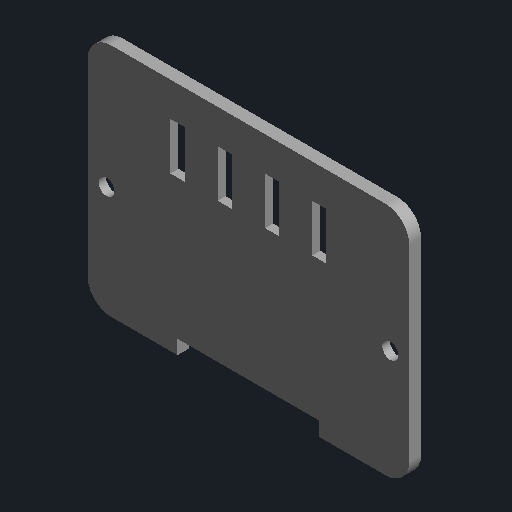
# Autodesk Inventor part: Torso_espalda
Saved by Autodesk Inventor 2027 (Build 310192060, 192F)
## iProperties
Part Number: Torso_espalda
Material: Genérico
Document SubType Name: Modelado
Designer: rodri
Appearance: Por defecto
Author: rodri
Autodesk Inventor part; units mm, degrees
ref_plane "Plano de trabajo1" through (0, 0, -29.2) normal (0, 0, 1) x (1, 0, 0)
sketch "Boceto1" plane through (0, 0, -29.2) normal (0, 0, 1) x (1, 0, 0)
  line L0 (-34, 8) -> (34, 8)
  line L1 (34, 8) -> (34, 57.7)
  line L2 (34, 57.7) -> (-34, 57.7)
  line L3 (-34, 57.7) -> (-34, 8)
  constraints: 8 end point, 2 parallel, 1 horizontal, 1 perpendicular
extrude "Extrusión1" add sketch "Boceto1" along normal blind 2.5
fillet "Empalme1" radius 5 4 edges at (-34, 8, -27.95) (-34, 57.7, -27.95) (34, 57.7, -27.95) (34, 8, -27.95)
ref_plane "Plano de trabajo2" through (0, 0, -29.3) normal (0, 0, 1) x (1, 0, 0)
sketch "Boceto2" plane through (0, 0, -29.3) normal (0, 0, 1) x (1, 0, 0)
  circle A0 centre (30, 31.3) radius 1.7
  circle A1 centre (-30, 31.3) radius 1.7
  constraints: 2 centre point
extrude "Extrusión2" cut sketch "Boceto2" along normal blind 2.7
ref_plane "Plano de trabajo3" through (0, 0, -29.3) normal (0, 0, 1) x (1, 0, 0)
sketch "Boceto3" plane through (0, 0, -29.3) normal (0, 0, 1) x (1, 0, 0)
  circle A0 centre (30, 31.3) radius 2.9
  circle A1 centre (-30, 31.3) radius 2.9
  constraints: 2 centre point
extrude "Extrusión3" cut sketch "Boceto3" along normal blind 1
ref_plane "Plano de trabajo4" through (0, 0, -29.3) normal (0, 0, 1) x (1, 0, 0)
sketch "Boceto4" plane through (0, 0, -29.3) normal (0, 0, 1) x (1, 0, 0)
  line L0 (-22, 38) -> (22, 38)
  line L1 (22, 38) -> (22, 53)
  line L2 (22, 53) -> (-22, 53)
  line L3 (-22, 53) -> (-22, 38)
  constraints: 8 end point, 2 parallel, 1 horizontal, 1 perpendicular
extrude "Extrusión4" cut sketch "Boceto4" along normal blind 0.9
ref_plane "Plano de trabajo5" through (0, 0, -29.3) normal (0, 0, 1) x (1, 0, 0)
sketch "Boceto5" plane through (0, 0, -29.3) normal (0, 0, 1) x (1, 0, 0)
  line L0 (-22, 14) -> (22, 14)
  line L1 (22, 14) -> (22, 26)
  line L2 (22, 26) -> (-22, 26)
  line L3 (-22, 26) -> (-22, 14)
  constraints: 8 end point, 2 parallel, 1 horizontal, 1 perpendicular
extrude "Extrusión5" cut sketch "Boceto5" along normal blind 0.9
ref_plane "Plano de trabajo6" through (0, 0, -29.3) normal (0, 0, 1) x (1, 0, 0)
sketch "Boceto6" plane through (0, 0, -29.3) normal (0, 0, 1) x (1, 0, 0)
  line L0 (-16.5, 40.5) -> (-13.5, 40.5)
  line L1 (-13.5, 40.5) -> (-13.5, 50.5)
  line L2 (-13.5, 50.5) -> (-16.5, 50.5)
  line L3 (-16.5, 50.5) -> (-16.5, 40.5)
  constraints: 8 end point, 2 parallel, 1 horizontal, 1 perpendicular
extrude "Extrusión6" cut sketch "Boceto6" along normal blind 2.7
ref_plane "Plano de trabajo7" through (0, 0, -29.3) normal (0, 0, 1) x (1, 0, 0)
sketch "Boceto7" plane through (0, 0, -29.3) normal (0, 0, 1) x (1, 0, 0)
  line L0 (-6.5, 40.5) -> (-3.5, 40.5)
  line L1 (-3.5, 40.5) -> (-3.5, 50.5)
  line L2 (-3.5, 50.5) -> (-6.5, 50.5)
  line L3 (-6.5, 50.5) -> (-6.5, 40.5)
  constraints: 8 end point, 2 parallel, 1 horizontal, 1 perpendicular
extrude "Extrusión7" cut sketch "Boceto7" along normal blind 2.7
ref_plane "Plano de trabajo8" through (0, 0, -29.3) normal (0, 0, 1) x (1, 0, 0)
sketch "Boceto8" plane through (0, 0, -29.3) normal (0, 0, 1) x (1, 0, 0)
  line L0 (3.5, 40.5) -> (6.5, 40.5)
  line L1 (6.5, 40.5) -> (6.5, 50.5)
  line L2 (6.5, 50.5) -> (3.5, 50.5)
  line L3 (3.5, 50.5) -> (3.5, 40.5)
  constraints: 8 end point, 2 parallel, 1 horizontal, 1 perpendicular
extrude "Extrusión8" cut sketch "Boceto8" along normal blind 2.7
ref_plane "Plano de trabajo9" through (0, 0, -29.3) normal (0, 0, 1) x (1, 0, 0)
sketch "Boceto9" plane through (0, 0, -29.3) normal (0, 0, 1) x (1, 0, 0)
  line L0 (13.5, 40.5) -> (16.5, 40.5)
  line L1 (16.5, 40.5) -> (16.5, 50.5)
  line L2 (16.5, 50.5) -> (13.5, 50.5)
  line L3 (13.5, 50.5) -> (13.5, 40.5)
  constraints: 8 end point, 2 parallel, 1 horizontal, 1 perpendicular
extrude "Extrusión9" cut sketch "Boceto9" along normal blind 2.7
ref_plane "Plano de trabajo10" through (0, 0, -29.3) normal (0, 0, 1) x (1, 0, 0)
sketch "Boceto10" plane through (0, 0, -29.3) normal (0, 0, 1) x (1, 0, 0)
  line L0 (-15, 7.9) -> (15, 7.9)
  line L1 (15, 7.9) -> (15, 11)
  line L2 (15, 11) -> (-15, 11)
  line L3 (-15, 11) -> (-15, 7.9)
  constraints: 8 end point, 2 parallel, 1 horizontal, 1 perpendicular
extrude "Extrusión10" cut sketch "Boceto10" along normal blind 2.7
ref_plane "Plano de trabajo11" through (0, 0, -29.9) normal (0, 0, 1) x (1, 0, 0)
sketch "Boceto11" plane through (0, 0, -29.9) normal (0, 0, 1) x (1, 0, 0)
  circle A0 centre (29, 12) radius 1.2
  circle A1 centre (29, 54) radius 1.2
  circle A2 centre (-29, 12) radius 1.2
  circle A3 centre (-29, 54) radius 1.2
  constraints: 4 centre point
extrude "Extrusión11" add sketch "Boceto11" along normal blind 0.71
ref_plane "Plano de trabajo12" through (0, 0, 0) normal (0, 1, 0) x (0, 0, 1)
ref_plane "Plano de trabajo13" through (0, 0, 0) normal (1, 0, 0) x (0, 0, -1)
